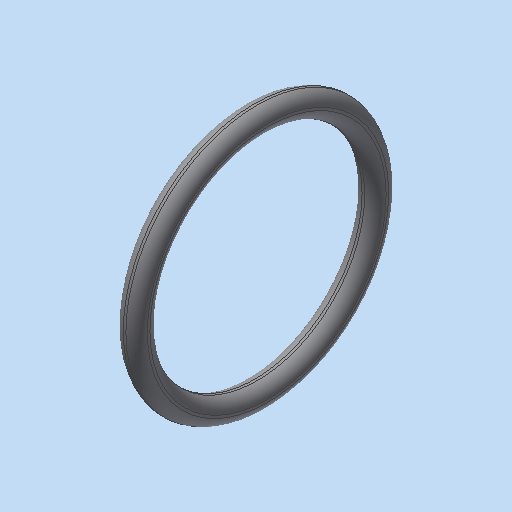
# Autodesk Inventor part: MM0885AN110_G02_121
Saved by Autodesk Inventor 2023.3 (Build 273359000, 359)
## iProperties
Part Number: MM0885AN110_G02_121
Document SubType Name: Modeling
Created: 2004-04-24
Description: =<RBPARTNOTITLE2>
Vendor: NORM8
Designer: C.Fischer
Manufacturer: Standard
Standards Organization: Custom
Density: 8.8 g/cm^3
Material: Generisch
Appearance: Vorgabe
Mass: 1.25029 g
Surface Area: 3.15966 cm^2
Volume: 0.142079 cm^3
Control State: 0
Master: False
Checked Out: False
Shininess: 64.0
Length Units: 11269
Angle Units: 11279
Time Units: 11290
Mass Units: 11283
Length Display Precision: 3
Angle Display Precision: 2
Compacted: True
CNS_NB: O-Ring DIN 3771 - 16x1.8-1.8-1.8
CNS_NN: DIN 3771
CNS_NT: O-Ringe
CNS_NBSYN: O-Ring DIN 3771 - $NENN.-$TA.-$TR.
CNS_LINA: O-Ring DIN 3771 - 16x1.8-1.8-1.8
CNS_D1: 16.000
CNS_D2: 1.800
CNS_NENN: 16x1.8
CNS_INN: 1.440
CNS_TA: 1.80
CNS_TR: 1.80
CNS_KT: DUMMY
PSOL_IDENT_0: {C:\partsolutions\data\23d-libs\bosch_bamberg\wellenelemente\dichtungen\ringe\din_3771.prj},158 {VTY
PSOL_IDENT_1: P=3D},{NB=O-Ring DIN 3771 - 16x1.8-1.8-1.8},{NN=DIN 3771},{DATE=26.11.2003},{GEOMDATE=26.11.2003},{V
PSOL_IDENT_2: ERSION=v1},{LINEID=370},{LINESUBID=-1},{WBVAR=TA,TR}  {NB=O-Ring DIN 3771 - 16x1.8-1.8-1.8},{LINA=O-
PSOL_IDENT_3: Ring DIN 3771 - 16x1.8-1.8-1.8},{KT=DUMMY},{IDNR=},{D1=16.000},{D2=1.800},{NENN=16x1.8},{INN=1.44},{
PSOL_IDENT_4: TA=1.8},{TR=1.8}
RBPARTNOTITLE2: O-Ring
RBPARTMADEOF: DIN 3771 - 16x1.8-1.8-1.8, NBR 70
RBDRAWINGMISSINGSPEC: --
AnP_Kategorie: 2
RBGBREMARKSINDEX: E
RBSURFACE: --
RBPARTNOTITLE1: o-ring
AnP_Material: =<Material>
RBMATERIAL: --
RBMATNO: =<Part Number>
RBSURFACE2: --
RBPARTNO: SIEHE MNR
Density: 0.0
Volumn: 0.0
Area: 0.0
PropertySet Name: Model Information
Title: O-Ring DIN 3771 - 16x1.8-1.8-1.8
Author: C.Fischer
Keywords: =<RBPARTMADEOF>
Comments: =<RBSURFACE2>
Revision Number: 01
Autodesk Inventor part; units mm, degrees
sketch "Sketch_1" plane through (0, 0, 0) normal (0, 0, 1) x (1, 0, 0)
  line L0 (0, 0) -> (1.79, 0)
  arc A0 (0, -8.9897) -> (0.8003, -9.79) centre (0.895, -8.895) ccw
  line L1 (0.8003, -9.79) -> (0.9897, -9.79)
  arc A1 (0.9897, -9.79) -> (1.79, -8.9897) centre (0.895, -8.895) ccw
  line L2 (1.79, -8.9897) -> (1.79, -8.8003)
  arc A2 (1.79, -8.8003) -> (0.9897, -8) centre (0.895, -8.895) ccw
  line L3 (0.9897, -8) -> (0.8003, -8)
  arc A3 (0.8003, -8) -> (0, -8.8003) centre (0.895, -8.895) ccw
  line L4 (0, -8.8003) -> (0, -8.9897)
  constraints: 10 end point, 8 point on circle, 4 centre point
revolve "Revolution1" add sketch "Sketch_1" angle 360 about axis through (0, 0, 0) along (1, 0, 0)
ref_plane "IP2_XY" through (0, 0, 0) normal (1, 0, 0) x (0, 0, -1)
ref_plane "IP2_YZ" through (0, 0, 0) normal (0, 0, -1) x (0, 1, 0)
ref_plane "IP3_XY" through (1.8, 0, 0) normal (1, 0, 0) x (0, 0, -1)
ref_plane "IP3_YZ" through (1.8, 0, 0) normal (0, 0, -1) x (0, 1, 0)
ref_plane "IP1_XY" through (0.9, 0, 0) normal (1, 0, 0) x (0, 0, -1)
ref_plane "IP1_YZ" through (0.9, 0, 0) normal (0, 0, -1) x (0, 1, 0)
